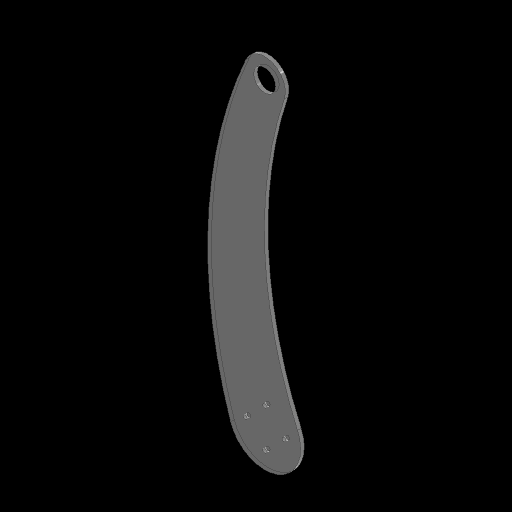
# Autodesk Inventor part: Part2
Saved by Autodesk Inventor 2027.1 (Build 311270010, 270A)
## iProperties
Created: 2026-11-12
Part Number: Part2
Material: Polycarbonate, Clear
Document SubType Name: Modeling
Designer: Stanley Ruangsuwan
Density: 1.2 g/cm^3
Appearance: Polycarbonate - Clear
Author: Stanley Ruangsuwan
Autodesk Inventor part; units mm, degrees
ref_plane "YZ Plane" through (0, 0, 0) normal (1, 0, 0) x (0, 1, 0)
ref_plane "XZ Plane" through (0, 0, 0) normal (0, 1, 0) x (-1, 0, 0)
ref_plane "XY Plane" through (0, 0, 0) normal (0, 0, 1) x (1, 0, 0)
sketch "Sketch1" plane through (0, 0, 0) normal (0, 0, 1) x (1, 0, 0)
  circle A0 centre (0, 393.6359) radius 14.2875
  circle A1 centre (0, 0) radius 34.29 construction
  circle A2 centre (0, 0) radius 46.99
  circle A3 centre (0, 393.6359) radius 26.9875
  arc A4 (-24.6839, 404.5461) -> (-44.5847, -14.8415) centre (507.997, 169.1034) ccw
  arc A5 (25.6061, 385.1121) -> (42.979, 18.9965) centre (507.997, 224.5325) ccw
  circle A6 centre (0, 0) radius 25.4 construction
  circle A7 centre (0, 25.4) radius 2.4892
  circle A8 centre (-25.4, 0) radius 2.4892
  circle A9 centre (0, -25.4) radius 2.4892
  circle A10 centre (25.4, 0) radius 2.4892
  dimension "d7" = 50.8
  dimension "d0" = 28.575
  dimension "d1" = 68.58
  dimension "d3" = 393.6359
  dimension "d4" = 12.7
  dimension "d5" = 12.7
  dimension "d6" = 508.416
  dimension "d8" = 4.9784
  dimension "d11" = 360
  constraints: 10 centre point, 8 point on circle, 4 tangent, 4 vertical alignment, 2 coincident, 11 other
  measures "d0" diameter of A0
  measures "d1" diameter of A1
  measures "d3" distance of A0.centre A1.centre
  measures "d4" radial gap between concentric circles of A1 A2
  measures "d5" radial gap between concentric circles of A0 A3
  measures "d6" radius of A5
  measures "d8" diameter of A7
extrude "Extrusion1" add sketch "Sketch1" along normal blind 4.7625
body "Solid1"
